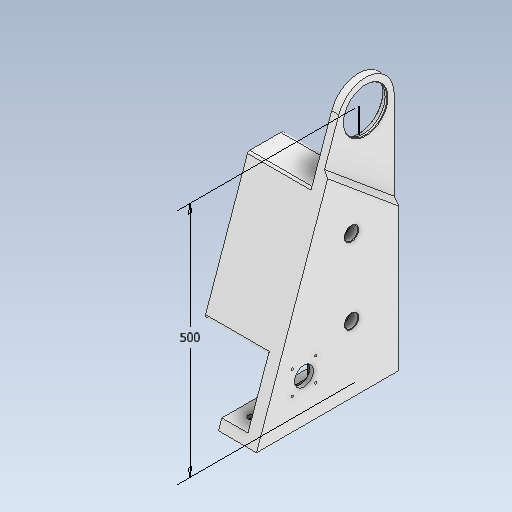
# Autodesk Inventor part: Part2
Saved by Autodesk Inventor 2021 (Build 250183000, 183)
## iProperties
Created: 2025-11-05
Part Number: Part2
Material: ABS Plastic
Document SubType Name: Modeling
Designer: Admin
Density: 1.06 g/cm^3
Appearance: Smooth - White
Mass: 4228.4 g
Surface Area: 4237.5 cm^2
Volume: 3989.05 cm^3
Author: Admin
Autodesk Inventor part; units mm, degrees
ref_plane "YZ Plane" through (0, 0, 0) normal (1, 0, 0) x (0, 1, 0)
sketch "Sketch2" plane through (0, 0, 0) normal (1, 0, 0) x (0, 1, 0)
  line L0 (0, 0) -> (-500, 0)
  dimension "d6" = 500
  constraints: 2 end point, 1 horizontal
  measures "d6" distance of L0.start L0.end
sketch "Sketch1" plane through (0, 0, 0) normal (0, 0, 1) x (1, 0, 0)
  line L0 (0, 50) -> (10, 50)
  line L1 (10, 50) -> (10, 46)
  line L2 (10, 46) -> (15, 46)
  line L3 (15, 46) -> (15, 60)
  line L4 (15, 60) -> (0, 60)
  line L5 (0, 60) -> (0, 50)
  line L6 (-3, 0) -> (18, 0) projected
  line L7 (0, -612) -> (0, 172) projected
  point P0 (0, 0)
  dimension "d0" = 60
  dimension "d1" = 50
  dimension "d2" = 5
  dimension "d3" = 10
  dimension "d4" = 4
  constraints: 13 end point, 5 perpendicular, 1 collinear, 1 horizontal
  measures "d0" distance between parallel lines of L6 L4
  measures "d1" distance between parallel lines of L6 L0
  measures "d2" distance of L1.end L2.end
  measures "d3" distance of L0.start L0.end
  measures "d4" distance between parallel lines of L2 L0
revolve "Revolution1" add sketch "Sketch1" angle 360 about axis through (0, 0, 0) along (1, 0, 0)
sketch "Sketch3" plane through (0, 0, 0) normal (1, 0, 0) x (0, 1, 0)
  circle A0 centre (0, 0) radius 60 projected
  line L0 (19.9597, 56.5828) -> (-500, 240)
  line L1 (-500, 240) -> (-500, -60)
  line L2 (-500, -60) -> (0, -60)
  arc A1 (19.9597, 56.5828) -> (0, -60) centre (0, 0) ccw
  point P0 (0, -60)
  dimension "d10" = 500
  dimension "d11" = 300
  constraints: 6 end point, 2 horizontal, 2 point on circle, 1 centre point, 1 coincident, 1 vertical, 3 other
  measures "d10" distance of L1.end L2.end
  measures "d11" distance of L0.end L1.end
extrude "Extrusion1" add sketch "Sketch3" along normal up to surface (15 mm away) contours A0 L2 L1 L0
sketch "Sketch4" plane through (0, 0, 0) normal (1, 0, 0) x (0, 1, 0)
  line L0 (-500, -60) -> (0, -60) projected
  line L1 (-400, -60) -> (-220, -60)
  line L2 (-220, -60) -> (-220, -35)
  line L3 (-220, -35) -> (-400, -35)
  line L4 (-400, -35) -> (-400, -60)
  line L5 (-500, 240) -> (-500, -60) projected
  line L6 (-100, 20) -> (-120, 20)
  line L7 (-120, 20) -> (-120, 105.9539)
  line L8 (19.9597, 56.5828) -> (-500, 240) projected
  line L9 (-100, 98.8989) -> (-100, 20)
  line L10 (-120, 105.9539) -> (-100, 98.8989)
  line L11 (-603.9919, 0) -> (123.9517, 0) projected
  line L12 (-220, 141.2292) -> (-220, 116.2292)
  line L13 (-220, 116.2292) -> (-360, 165.6146)
  line L14 (-360, 165.6146) -> (-360, 190.6146)
  line L15 (-220, 141.2292) -> (-360, 190.6146)
  point P0 (0, 0)
  dimension "d12" = 180
  dimension "d13" = 100
  dimension "d14" = 25
  dimension "d15" = 20
  dimension "d53" = 20
  dimension "d54" = 380
  dimension "d87" = 25
  dimension "d88" = 100
  dimension "d89" = 140
  constraints: 24 end point, 5 point on line, 4 parallel, 3 perpendicular, 2 horizontal, 1 vertical
  measures "d12" distance between parallel lines of L2 L4
  measures "d13" distance between parallel lines of L5 L4
  measures "d14" distance of L1.end L2.end
  measures "d15" distance between parallel lines of L9 L7
  measures "d53" distance between parallel lines of L11 L6
  measures "d54" distance between parallel lines of L5 L7
  measures "d87" distance of L12.start L12.end
  measures "d88" distance between parallel lines of L12 L7
  measures "d89" distance between parallel lines of L5 L14
extrude "Extrusion2" add sketch "Sketch4" against normal blind 134
sketch "Sketch5" plane through (0, 0, 0) normal (1, 0, 0) x (0, 1, 0)
  circle A0 centre (-410, 140) radius 60 construction
  line L0 (-500, 240) -> (-500, -60) projected
  line L1 (-600, 0) -> (100, 0) projected
  line L2 (-360, 40) -> (-178.1459, 40) construction
  point P0 (0, 0)
  point P1 (-300, 115)
  point P2 (-200, 40)
  dimension "d19" = 120
  dimension "d20" = 90
  dimension "d21" = 140
  dimension "d22" = 100
  dimension "d23" = 140
  dimension "d24" = 200
  dimension "d25" = 300
  dimension "d26" = 75
  constraints: 2 end point, 1 centre point, 1 coincident, 1 horizontal, 1 point on line
  measures "d19" diameter of A0
  measures "d20" distance from line of L0 point (-410, 140)
  measures "d21" distance from line of L1 point (-410, 140)
  measures "d22" vertical distance of L2.start point (-410, 140)
  measures "d23" distance from line of L0 L2.start
  measures "d24" distance from line of L0 point (-300, 115)
  measures "d25" distance from line of L0 point (-200, 40)
  measures "d26" distance from line of point (-300, 115) L2
sketch "Sketch6" plane through (15, -500, -60) normal (1, 0, 0) x (0, 0, -1)
  line L0 (-300, 0) -> (-116.5828, 519.9597) projected
  line L1 (-300, 0) -> (-150.0801, 425)
  line L2 (-300, 0) -> (0, 0)
  line L3 (0, 0) -> (0, 300)
  line L4 (0, 280) -> (0, 500) projected
  line L5 (0, 500) -> (0, 0) projected
  line L6 (-150.0801, 425) -> (0, 300)
  point P0 (-60, 500)
  dimension "d33" = 425
  dimension "d34" = 300
  constraints: 8 end point, 2 point on line, 1 collinear, 1 horizontal
  measures "d33" distance from line of L2 L1.end
  measures "d34" distance of L2.end L3.end
extrude "Extrusion3" add sketch "Sketch6" along normal blind 10
chamfer "Chamfer1" distance 10 angle 45 1 edges at (15, -137.5, 15.04)
sketch "Sketch7" plane through (0, 0, 0) normal (1, 0, 0) x (0, 1, 0)
  line L0 (-442, 172) -> (-378, 172)
  line L1 (-378, 172) -> (-378, 108)
  line L2 (-378, 108) -> (-442, 108)
  line L3 (-442, 108) -> (-442, 172)
  line L4 (-442, 172) -> (-378, 108) construction
  line L5 (-378, 172) -> (-442, 108) construction
  point P0 (0, 0)
  point P1 (-410, 140)
  point P2 (-410, 140)
  point P3 (-410, 140)
  dimension "d35" = 64
  constraints: 12 end point, 3 midpoint, 2 parallel, 2 perpendicular, 1 coincident, 1 horizontal
  measures "d35" distance between parallel lines of L3 L1
extrude "Extrusion4" cut sketch "Sketch7" along normal blind 13
ref_plane "Work Plane1" through (0, -410, 140) normal (0, 1, 0) x (-1, 0, 0)
sketch "Sketch8" plane through (0, -410, 140) normal (0, 1, 0) x (-1, 0, 0)
  line L0 (-13, -28) -> (-16, -28)
  line L1 (-16, -28) -> (-16, -20)
  line L2 (-16, -20) -> (-25, -20)
  line L3 (-25, -20) -> (-25, 0)
  line L4 (-25, 0) -> (-13, 0)
  line L5 (-13, 32) -> (-13, -32) projected
  line L6 (-13, -28) -> (-13, 0)
  line L7 (-25, 100) -> (-25, -200) projected
  line L8 (-56.8, 0) -> (165.8, 0) projected
  point P0 (0, -140)
  point P1 (-13, -28)
  dimension "d39" = 28
  dimension "d40" = 20
  dimension "d41" = 3
  constraints: 12 end point, 3 collinear, 3 perpendicular, 1 horizontal, 1 midpoint
  measures "d39" distance between parallel lines of L4 L0
  measures "d40" distance between parallel lines of L8 L2
  measures "d41" distance of L0.start L0.end
revolve "Revolution2" cut sketch "Sketch8" angle 360 about axis through (25, -410, 140) along (-1, 0, 0)
sketch "Sketch9" plane through (13, 0, 0) normal (-1, 0, 0) x (0, 0, 1)
  circle A0 centre (140, -410) radius 20 projected
  circle A1 centre (140, -410) radius 35
  line L0 (115.2513, -385.2513) -> (164.7487, -434.7487)
  line L1 (115.2513, -434.7487) -> (164.7487, -385.2513)
  line L2 (-120, -410) -> (300, -410) projected
  point P0 (0, 0)
  dimension "d43" = 70
  dimension "d44" = 45
  dimension "d45" = 45
  constraints: 4 end point, 4 point on circle, 3 midpoint, 1 centre point, 1 coincident
  measures "d43" diameter of A1
  measures "d44" angle of L2 L1
  measures "d45" angle of L2 L0
hole "Hole1" at (13, -385.2513, 115.2513) at (13, -385.2513, 164.7487) at (13, -434.7487, 164.7487) at (13, -434.7487, 115.2513) direction (1, 0, 0) diameter 4.5 end through all clearance for "Hex Head Cap Screw ISO 24017" size "M4" standard "ISO"
ref_plane "Work Plane2" through (0, -200, 40) normal (0, 1, 0) x (-1, 0, 0)
sketch "Sketch10" plane through (0, -200, 40) normal (0, 1, 0) x (-1, 0, 0)
  line L0 (0, 200) -> (0, -100) projected
  line L1 (0, -15) -> (-7, -15)
  line L2 (-7, -15) -> (-7, -14)
  line L3 (-7, -14) -> (-25, -14)
  line L4 (-25, 0) -> (0, 0)
  line L5 (0, 0) -> (0, -15)
  line L6 (-56.8, 0) -> (165.8, 0) projected
  line L7 (-25, -14) -> (-25, 0)
  line L8 (-25, 200) -> (-25, -100) projected
  point P0 (0, -40)
  point P1 (0, 0)
  dimension "d56" = 15
  dimension "d57" = 1
  dimension "d58" = 7
  constraints: 12 end point, 4 perpendicular, 2 collinear, 2 horizontal, 2 point on line
  measures "d56" distance between parallel lines of L4 L1
  measures "d57" distance between parallel lines of L3 L1
  measures "d58" distance of L1.start L1.end
revolve "Revolution3" cut sketch "Sketch10" angle 360 about axis through (0, -200, 40) along (-1, 0, 0)
fillet "Fillet1" radius 10 2 edges at (-67, -100, 20) (-67, -120, 20)
chamfer "Chamfer6" distance 5 angle 45 1 edges at (-67, -220, -60)
sketch "Sketch11" plane through (0, -500, -60) normal (-1, 0, 0) x (0, 0, 1)
  line L0 (300, 0) -> (0, 0) projected
  line L1 (0, 0) -> (300, 0)
  line L2 (300, 0) -> (292.9449, 20)
  line L3 (165.9539, 380) -> (300, 0) projected
  line L4 (292.9449, 20) -> (0, 20)
  line L5 (0, 0) -> (0, 300) projected
  line L6 (0, 0) -> (0, 20)
  point P0 (60, 500)
  dimension "d78" = 20
  constraints: 8 end point, 2 point on line, 1 horizontal, 1 parallel, 1 perpendicular
  measures "d78" distance between parallel lines of L0 L4
extrude "Extrusion5" add sketch "Sketch11" along normal blind 55
ref_plane "Work Plane3" through (0, -360, 40) normal (0, 1, 0) x (-1, 0, 0)
sketch "Sketch12" plane through (0, -360, 40) normal (0, 1, 0) x (-1, 0, 0)
  line L0 (0, -100) -> (0, 192.9449) projected
  line L1 (0, -15) -> (-7, -15)
  line L2 (-7, -15) -> (-7, -14)
  line L3 (-7, -14) -> (-25, -14)
  line L4 (-25, -14) -> (-25, 0)
  line L5 (-25, 200) -> (-25, -100) projected
  line L6 (-25, 0) -> (0, 0)
  line L7 (0, 0) -> (0, -15)
  line L8 (-56.8, 0) -> (165.8, 0) projected
  point P0 (0, -40)
  point P1 (0, 0)
  dimension "d82" = 15
  dimension "d83" = 7
  dimension "d84" = 18
  dimension "d85" = 1
  constraints: 12 end point, 4 perpendicular, 2 point on line, 1 collinear, 1 horizontal
  measures "d82" distance between parallel lines of L6 L1
  measures "d83" distance of L1.start L1.end
  measures "d84" distance of L2.end L3.end
  measures "d85" distance between parallel lines of L3 L1
revolve "Revolution4" cut sketch "Sketch12" angle 360 about axis through (25, -360, 40) along (-1, 0, 0)
sketch "Sketch13" plane through (-134, 0, 0) normal (-1, 0, 0) x (0, 0, 1)
  line L0 (-60, -400) -> (-35, -400) projected
  line L1 (-47.5, -400) -> (-47.5, -220)
  line L2 (-35, -220) -> (-55, -220) projected
  arc A0 (30, -100) -> (30, -120) centre (30, -110) ccw projected
  line L3 (20, -110) -> (102.4264, -110)
  line L4 (90.0801, -75) -> (240, -500) projected
  line L5 (141.2292, -220) -> (116.2292, -220) projected
  line L6 (128.7292, -220) -> (178.1146, -360)
  line L7 (190.6146, -360) -> (165.6146, -360) projected
  point P0 (0, 0)
  point P1 (85, -110)
  point P2 (-47.5, -240)
  point P3 (-47.5, -380)
  point P4 (135.7843, -240)
  point P5 (171.0596, -340)
  point P6 (-47.5, -310)
  dimension "d90" = 20
  dimension "d91" = 20
  dimension "d92" = 55
  dimension "d93" = 20
  dimension "d94" = 20
  constraints: 7 point on line, 6 end point, 4 midpoint, 1 coincident, 1 perpendicular, 1 point on circle, 1 vertical
  measures "d90" distance from line of L2 point (-47.5, -240)
  measures "d91" distance from line of L0 point (-47.5, -380)
  measures "d92" distance of point (30, -110) point (85, -110)
  measures "d93" distance from line of L5 point (135.784, -240)
  measures "d94" distance from line of L7 point (171.06, -340)
hole "Hole2" at (-134, -240, -47.5) at (-134, -310, -47.5) at (-134, -380, -47.5) at (-134, -110, 30) at (-134, -110, 85) at (-134, -240, 135.7843) at (-134, -340, 171.0596) direction (1, 0, 0) diameter 8 depth 15
sketch "Sketch14" plane through (0, -480, 232.9449) normal (0, 1, 0) x (1, 0, 0)
  line L0 (0, 292.9449) -> (-134, 292.9449) projected
  line L1 (-55, -7.0551) -> (25, -7.0551) projected
  line L2 (25, 142.8649) -> (25, -7.0551) projected
  line L3 (25, 292.9449) -> (25, 142.8649) projected
  point P0 (0, 232.9449)
  point P1 (-25, 252.9449)
  point P2 (-25, 32.9449)
  dimension "d102" = 40
  dimension "d103" = 40
  dimension "d104" = 50
  dimension "d105" = 50
  measures "d102" distance from line of L0 point (-25, 252.945)
  measures "d103" distance from line of L1 point (-25, 32.945)
  measures "d104" distance from line of L2 point (-25, 32.945)
  measures "d105" distance from line of L3 point (-25, 252.945)
hole "Hole3" at (-25, -480, -20) at (-25, -480, 200) direction (0, -1, 0) diameter 9 end through all counterbore diameter 15 counterbore depth 8 clearance for "Socket Head Cap Screw ISO 4762" size "M8" standard "ISO"
fillet "Fillet3" radius 5 9 edges at (-67, -220, 116.2292) (-67, -220, 141.2292) (-67, -360, 165.6146) (-67, -360, 190.6146) (-67, -400, -60) (-67, -400, -35) (-67, -220, -35) (-67, -100, 98.8989) (-67, -120, 105.9539)
fillet "Fillet4" radius 0.2 1 edges at (7, -200, 55)
fillet "Fillet5" radius 0.2 1 edges at (7, -360, 55)
fillet "Fillet6" radius 0.4 1 edges at (10, -50, 0)
sketch "Sketch16" plane through (0, -110, 30) normal (-1, 0, 0) x (0, 0, 1)
  line L0 (60.0801, 35) -> (210, -390) projected
  line L1 (113.2857, -115.8298) -> (109.0441, -115.8298)
  line L2 (109.0441, -115.8298) -> (69.4094, -3.4714)
  line L3 (69.4094, -3.4714) -> (73.1816, -2.1408)
  line L4 (68.8882, -10) -> (0, -10) projected
  line L5 (66.2343, -10) -> (71.7124, -10)
  line L6 (70.6395, -6.9587) -> (66.2343, -10)
  point P0 (-30, 110)
  dimension "d117" = 4
  constraints: 10 end point, 5 point on line, 1 collinear, 1 horizontal, 1 parallel, 1 perpendicular
  measures "d117" distance between parallel lines of L0 L2
extrude "Extrusion6" add sketch "Sketch16" along normal up to surface (134 mm away)
fillet "Fillet7" radius 4 2 edges at (-67, -120, 101.7124) (-67, -220, 136.9876)
chamfer "Chamfer7" distance 1 angle 45 7 edges at (0, -50, 0) (0, -200, 55) (0, -360, 55) (16, -410, 160) (25, -360, 54) (25, -200, 54) (15, -46, 0)
equation "\"d10\" = d6"
body "Solid1"
